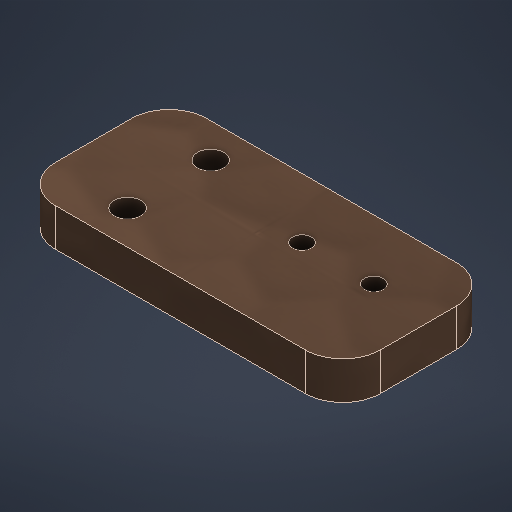
# Autodesk Inventor part: LimitSwitchMountPlate
Saved by Autodesk Inventor 2027.1 (Build 311270010, 270A)
## iProperties
Created: 2026-10-16
Part Number: LimitSwitchMountPlate
Material: MDF Medium Density Fiberboard
Document SubType Name: Modeling
Designer: SDS Scholar
Density: 0.8 g/cm^3
Appearance: Bronze - Satin Hammered
Author: SDS Scholar
Autodesk Inventor part; units mm, degrees
ref_plane "YZ Plane" through (0, 0, 0) normal (1, 0, 0) x (0, 1, 0)
ref_plane "XZ Plane" through (0, 0, 0) normal (0, 1, 0) x (-1, 0, 0)
ref_plane "XY Plane" through (0, 0, 0) normal (0, 0, 1) x (1, 0, 0)
sketch "Sketch1" plane through (0, 0, 0) normal (0, 1, 0) x (-1, 0, 0)
  line L0 (18, 10) -> (-15, 10)
  line L1 (-20, 5) -> (-20, -5)
  line L2 (-15, -10) -> (20, -10)
  circle A0 centre (-2.5, -2.1) radius 1.25
  circle A1 centre (-12, -2.1) radius 1.25
  arc A2 (-15, 10) -> (-20, 5) centre (-15, 5) ccw
  arc A3 (-20, -5) -> (-15, -10) centre (-15, -5) ccw
  circle A4 centre (13, -5.5) radius 1.75
  circle A5 centre (13, 5.5) radius 1.75
  line L3 (20, 0) -> (-20, 0) construction
  line L4 (23, -5) -> (23, 5)
  line L5 (18, 10) -> (20, 10)
  line L6 (20, -10) -> (18, -10)
  arc A6 (18, -10) -> (23, -5) centre (18, -5) ccw
  arc A7 (23, 5) -> (18, 10) centre (18, 5) ccw
  point P0 (0, 0)
  point P1 (-20, -10)
  point P2 (-20, 10)
  point P3 (0, -10)
  dimension "d0" = 40
  dimension "d1" = 20
  dimension "d2" = 2.5
  dimension "d3" = 2.5
  dimension "d4" = 9.5
  dimension "d5" = 7.9
  dimension "d6" = 8
  dimension "d7" = 5
  dimension "d10" = 3.5
  dimension "d11" = 3.5
  dimension "d13" = 4.5
  dimension "d14" = 3
  dimension "d15" = 43
  dimension "d16" = 23
  dimension "d17" = 3
  dimension "d18" = 10
  dimension "d19" = 5
  constraints: 14 end point, 8 centre point, 8 point on circle, 8 tangent, 5 point on line, 2 equal radius, 2 horizontal, 2 horizontal alignment, 2 vertical alignment, 1 collinear, 1 midpoint, 1 parallel, 1 perpendicular, 1 symmetric about line, 1 vertical
  measures "d0" distance of L2.end point (-20, -10)
  measures "d1" distance of point (-20, 10) point (-20, -10)
  measures "d2" diameter of A0
  measures "d3" diameter of A1
  measures "d4" distance of A1.centre A0.centre
  measures "d5" distance from line of L2 A0.centre
  measures "d6" distance from line of L1 A1.centre
  measures "d7" radius of A2
  measures "d10" diameter of A4
  measures "d11" diameter of A5
  measures "d13" distance from line of L2 A4.centre
  measures "d14" distance from line of L5.end L4
  measures "d15" distance between parallel lines of L4 L1
  measures "d16" distance from line of point (0, 0) L4
  measures "d17" distance from line of L3.start L4
  measures "d18" distance from line of A5.centre L4
  measures "d19" radius of A6
extrude "Extrusion1" add sketch "Sketch1" along normal blind 5
body "Solid1"
